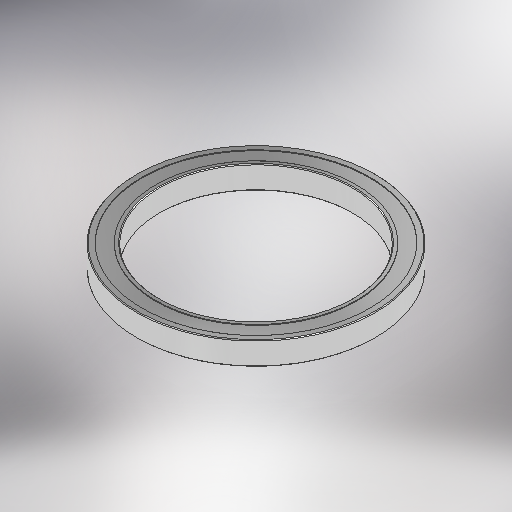
# Autodesk Inventor part: bearing-50-62
Saved by Autodesk Inventor 2025.3 (Build 293356030, 356C)
## iProperties
Created: 2026-05-05
Part Number: bearing-50-62
Material: 一般
Document SubType Name: Modeling
Designer: ibuki_ono
Density: 1 g/cm^3
Appearance: クロム - つや出し
Author: ibuki_ono
Autodesk Inventor part; units mm, degrees
ref_plane "YZ Plane" through (0, 0, 0) normal (1, 0, 0) x (0, 1, 0)
ref_plane "XZ Plane" through (0, 0, 0) normal (0, 1, 0) x (-1, 0, 0)
ref_plane "XY Plane" through (0, 0, 0) normal (0, 0, 1) x (1, 0, 0)
sketch "スケッチ1" plane through (0, 0, 0) normal (0, 1, 0) x (-1, 0, 0)
  circle A0 centre (0, 0) radius 31
  circle A1 centre (0, 0) radius 25
  dimension "d0" = 62
  dimension "d1" = 50
  constraints: 2 centre point, 2 coincident
  measures "d0" diameter of A0
  measures "d1" diameter of A1
extrude "押し出し1" add sketch "スケッチ1" along normal mid plane 6
chamfer "面取り1" distance 0.2 angle 45 4 edges at (31, 3, 0) (31, -3, 0) (25, 3, 0) (25, -3, 0)
sketch "スケッチ2" plane through (0, 3, 0) normal (0, 1, 0) x (1, 0, 0)
  circle A0 centre (0, 0) radius 31 projected
  circle A1 centre (0, 0) radius 25 projected
  circle A2 centre (0, 0) radius 29.5
  circle A3 centre (0, 0) radius 26
  dimension "d7" = 1.5
  dimension "d8" = 1
  constraints: 2 centre point
  measures "d7" radial gap between concentric circles of A0 A2
  measures "d8" radial gap between concentric circles of A1 A3
extrude "押し出し2" cut sketch "スケッチ2" against normal blind 0.2 contours A2
mirror "ミラー1" about plane through (0, 0, 0) normal (0, 1, 0) of "押し出し2"
